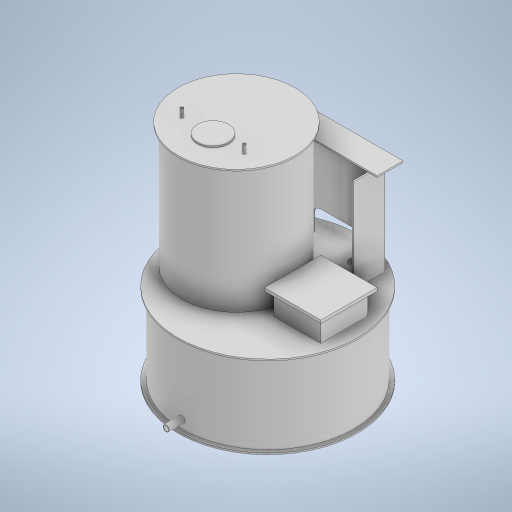
# Autodesk Inventor part: СДР 070 2хЕмкость
Saved by Autodesk Inventor 2023 (Build 270158000, 158)
## iProperties
Created: 2024-04-03
Part Number: СДР 070 2хЕмкость
Material: Типовые
Document SubType Name: Modeling
Designer: pokla
Density: 1 g/cm^3
Appearance: По умолчанию
Author: pokla
Autodesk Inventor part; units mm, degrees
ref_plane "YZ Plane" through (0, 0, 0) normal (1, 0, 0) x (0, 1, 0)
ref_plane "XZ Plane" through (0, 0, 0) normal (0, 1, 0) x (-1, 0, 0)
ref_plane "XY Plane" through (0, 0, 0) normal (0, 0, 1) x (1, 0, 0)
sketch "Эскиз1" plane through (0, 0, 0) normal (0, 1, 0) x (-1, 0, 0)
  circle A0 centre (0, 0) radius 575
  dimension "d0" = 1150
  constraints: 1 centre point, 1 coincident
  measures "d0" diameter of A0
extrude "Выдавливание1" add sketch "Эскиз1" along normal blind 10
sketch "Эскиз2" plane through (0, 10, 0) normal (0, 1, 0) x (1, 0, 0)
  circle A0 centre (0, 0) radius 550
  dimension "d3" = 1100
  constraints: 1 centre point, 1 coincident
  measures "d3" diameter of A0
extrude "Выдавливание2" add sketch "Эскиз2" along normal blind 510
sketch "Эскиз3" plane through (0, 520, 0) normal (0, 1, 0) x (1, 0, 0)
  circle A0 centre (0, 0) radius 575
  dimension "d6" = 1150
  constraints: 1 centre point, 1 coincident
  measures "d6" diameter of A0
extrude "Выдавливание3" add sketch "Эскиз3" along normal blind 10
sketch "Эскиз4" plane through (0, 530, 0) normal (0, 1, 0) x (1, 0, 0)
  circle A0 centre (0, 0) radius 550 projected
  circle A1 centre (0, 0) radius 550 projected
  line L0 (-840.1304, 0) -> (1197.9303, 0) construction
  circle A2 centre (-200, 0) radius 350
  dimension "d14" = 700
  dimension "d15" = 200
  constraints: 2 end point, 1 centre point, 1 horizontal, 1 horizontal alignment, 1 point on line
  measures "d14" diameter of A2
  measures "d15" distance of point (0, 0) A2.centre
extrude "Выдавливание4" add sketch "Эскиз4" along normal blind 800 contours A2
sketch "Эскиз5" plane through (-200, 1330, 0) normal (0, 1, 0) x (1, 0, 0)
  circle A0 centre (0, 0) radius 375
  point P0 (200, 0)
  dimension "d18" = 750
  constraints: 1 centre point
  measures "d18" diameter of A0
extrude "Выдавливание5" add sketch "Эскиз5" along normal blind 10
sketch "Эскиз7" plane through (0, 530, 0) normal (0, 1, 0) x (1, 0, 0)
  line L0 (190, 150) -> (490, 150)
  line L1 (490, 150) -> (490, -150)
  line L2 (490, -150) -> (190, -150)
  line L3 (190, -150) -> (190, 150)
  circle A0 centre (0, 0) radius 550 projected
  circle A1 centre (-200, 0) radius 350 projected
  point P0 (490, 0)
  point P1 (190, 0)
  dimension "d23" = 300
  dimension "d24" = 190
  constraints: 8 end point, 2 midpoint, 2 parallel, 2 perpendicular, 1 horizontal, 1 horizontal alignment
  measures "d23" distance of L1.end L2.end
  measures "d24" distance of point (0, 0) point (190, 0)
extrude "Выдавливание6" add sketch "Эскиз7" along normal blind 140 contours L0 L1 L2 L3
sketch "Эскиз8" plane through (0, 670, 0) normal (0, 1, 0) x (1, 0, 0)
  line L0 (190, -150) -> (490, -150) projected
  line L1 (490, -150) -> (490, 150) projected
  line L2 (490, 150) -> (190, 150) projected
  line L3 (190, 150) -> (190, -150) projected
  line L4 (160, 180) -> (520, 180)
  line L5 (520, 180) -> (520, -180)
  line L6 (520, -180) -> (160, -180)
  line L7 (160, -180) -> (160, 180)
  point P0 (0, 0)
  dimension "d27" = 30
  constraints: 8 end point, 3 other
  measures "d27" distance between parallel lines of L2 L4
extrude "Выдавливание7" add sketch "Эскиз8" along normal blind 20 contours L3 L2 L1 L0 | L4 L5 L6 L7
sketch "Эскиз9" plane through (0, 530, 0) normal (0, 1, 0) x (1, 0, 0)
  circle A0 centre (0, 0) radius 550 projected
  line L0 (490, 150) -> (190, 150) projected
  line L1 (190, 150) -> (190, -150) projected
  circle A1 centre (-200, 0) radius 350 construction
  line L2 (-300, 350) -> (-300, 450)
  line L3 (-300, 450) -> (300, 450)
  line L4 (300, 450) -> (300, 250)
  line L5 (290, 250) -> (290, 440)
  line L6 (290, 440) -> (-290, 440)
  line L7 (-290, 440) -> (-290, 350)
  line L8 (-290, 350) -> (-300, 350)
  line L9 (300, 250) -> (290, 250)
  dimension "d40" = 100
  dimension "d41" = 200
  dimension "d42" = 600
  dimension "d43" = 300
  dimension "d44" = 450
  dimension "d45" = 10
  constraints: 16 end point, 4 perpendicular, 1 horizontal, 1 parallel, 1 vertical, 2 other
  measures "d40" distance of L2.start L2.end
  measures "d41" distance of L3.end L4.end
  measures "d42" distance of L2.end L3.end
  measures "d43" distance from line of point (0, 0) L2
  measures "d44" distance from line of point (0, 0) L3
  measures "d45" distance between parallel lines of L4 L5
extrude "Выдавливание8" add sketch "Эскиз9" along normal blind 600 contours L2 L3 L4 L9 L5 L6 L7 L8
sketch "Эскиз11" plane through (0, 1130, 0) normal (0, 1, 0) x (1, 0, 0)
  line L0 (-300, 350) -> (-300, 450) projected
  line L1 (-300, 350) -> (300, 350) construction
  line L2 (300, 450) -> (300, 250) projected
  line L3 (-350, 515) -> (350, 515)
  line L4 (350, 515) -> (350, 350)
  line L5 (350, 350) -> (-350, 350)
  line L6 (-350, 350) -> (-350, 515)
  point P0 (0, 0)
  point P1 (0, 350)
  dimension "d52" = 700
  dimension "d53" = 165
  constraints: 10 end point, 3 midpoint, 2 parallel, 1 horizontal, 1 perpendicular
  measures "d52" distance of L3.start L3.end
  measures "d53" distance of L3.end L4.end
extrude "Выдавливание10" add sketch "Эскиз11" along normal blind 10
sketch "Эскиз12" plane through (300, 530, -450) normal (0, 0, -1) x (-1, 0, 0)
  line L0 (600, 0) -> (0, 0) projected
  line L1 (600, 0) -> (600, 600) projected
  line L2 (0, 600) -> (600, 600) projected
  line L3 (0, 0) -> (0, 600) projected
  line L4 (10, 0) -> (590, 0) projected
  line L5 (150, 0) -> (150, 155)
  line L6 (150, 155) -> (450, 155)
  line L7 (450, 155) -> (450, 0)
  line L8 (500, 600) -> (10, 600) projected
  point P0 (300, -530)
  point P1 (450, 56.6393)
  dimension "d58" = 300
  dimension "d59" = 155
  dimension "d61" = 150
  constraints: 6 end point, 3 point on line, 2 perpendicular
  measures "d58" distance between parallel lines of L7 L5
  measures "d59" distance between parallel lines of L0 L6
  measures "d61" distance from line of L1 point (450, 56.639)
extrude "Выдавливание11" cut sketch "Эскиз12" against normal up to surface (10 mm away) contours L0 L5 L6 L7
fillet "Сопряжение1" radius 50 2 edges at (150, 685, -445) (-150, 685, -445)
sketch "Эскиз13" plane through (0, 530, 0) normal (0, 1, 0) x (1, 0, 0)
  line L0 (150, 450) -> (150, 440) projected
  line L1 (-150, 450) -> (-150, 440) projected
  circle A0 centre (150, 400) radius 30
  line L2 (150, 440) -> (-150, 440) construction
  line L3 (-190, 450) -> (-190, 400) construction
  line L4 (-190, 400) -> (190, 400) construction
  line L5 (190, 400) -> (190, 450) construction
  line L6 (150, 440) -> (150, 328.7741) construction
  line L7 (-150, 440) -> (-150, 308.6915) construction
  circle A1 centre (-150, 400) radius 27.5
  circle A2 centre (150, 400) radius 25
  circle A3 centre (-150, 400) radius 22.5
  point P0 (0, 0)
  dimension "d66" = 60
  dimension "d67" = 40
  dimension "d68" = 55
  dimension "d69" = 5
  dimension "d70" = 5
  constraints: 12 end point, 4 centre point, 4 point on line, 2 coincident, 2 vertical, 1 horizontal, 2 other
  measures "d66" diameter of A0
  measures "d67" distance between parallel lines of L2 L4
  measures "d68" diameter of A1
  measures "d69" radial gap between concentric circles of A0 A2
  measures "d70" radial gap between concentric circles of A1 A3
extrude "Выдавливание12" add sketch "Эскиз13" along normal blind 10
sketch "Эскиз14" plane through (-150, 530, -400) normal (0, 1, 0) x (1, 0, 0)
  circle A0 centre (300, 0) radius 25 projected
  circle A1 centre (0, 0) radius 22.5 projected
  point P0 (150, -400)
extrude "Выдавливание13" cut sketch "Эскиз14" against normal blind 30
sketch "Эскиз15" plane through (0, 0, 0) normal (0, 0, 1) x (1, 0, 0)
  line L0 (575, 0) -> (-575, 0) projected
  circle A0 centre (0, 65) radius 20
  circle A1 centre (0, 65) radius 15
  point P0 (0, 0)
  point P1 (0, 0)
  dimension "d75" = 40
  dimension "d76" = 65
  dimension "d77" = 5
  constraints: 2 centre point, 1 midpoint, 1 vertical alignment
  measures "d75" diameter of A0
  measures "d76" distance of point (0, 0) A0.centre
  measures "d77" radial gap between concentric circles of A0 A1
extrude "Выдавливание14" add sketch "Эскиз15" along normal blind 650
sketch "Эскиз16" plane through (0, 0, 0) normal (1, 0, 0) x (0, 1, 0)
  line L0 (0, -575) -> (0, 575) projected
  circle A0 centre (65, 0) radius 20
  circle A1 centre (65, 0) radius 15
  line L1 (530, 350) -> (530, -350) projected
  circle A2 centre (590, 0) radius 20
  circle A3 centre (590, 0) radius 15
  point P0 (0, 0)
  point P1 (0, 0)
  point P2 (530, 0)
  dimension "d80" = 40
  dimension "d81" = 65
  dimension "d82" = 5
  dimension "d83" = 40
  dimension "d84" = 60
  dimension "d85" = 5
  constraints: 4 centre point, 2 horizontal alignment, 2 midpoint
  measures "d80" diameter of A0
  measures "d81" distance of point (0, 0) A0.centre
  measures "d82" radial gap between concentric circles of A0 A1
  measures "d83" diameter of A2
  measures "d84" distance of point (530, 0) A2.centre
  measures "d85" radial gap between concentric circles of A2 A3
extrude "Выдавливание15" add sketch "Эскиз16" against normal blind 650
sketch "Эскиз17" plane through (-200, 1340, 0) normal (0, 1, 0) x (1, 0, 0)
  circle A0 centre (0, 0) radius 350 projected
  circle A1 centre (200, 0) radius 550 construction
  line L0 (-350, 0) -> (350, 0) construction
  line L1 (360, 180) -> (360, -180) construction
  circle A2 centre (0, -150) radius 100
  dimension "d88" = 200
  dimension "d89" = 150
  constraints: 2 end point, 2 point on circle, 1 centre point, 1 horizontal alignment, 1 midpoint, 1 perpendicular, 1 vertical alignment, 1 other
  measures "d88" diameter of A2
  measures "d89" distance of A0.centre A2.centre
extrude "Выдавливание16" add sketch "Эскиз17" along normal blind 10 contours A2
sketch "Эскиз18" plane through (-200, 1340, 0) normal (0, 1, 0) x (1, 0, 0)
  circle A0 centre (0, -150) radius 100 projected
  circle A1 centre (0, 0) radius 350 projected
  circle A2 centre (200, 0) radius 550 construction
  line L0 (-350, 0) -> (350, 0) construction
  line L1 (360, 180) -> (360, -180) construction
  circle A3 centre (-200, -150) radius 10
  line L2 (0, -150) -> (-457.1961, -150) construction
  line L3 (0, -150) -> (489.8773, -150) construction
  circle A4 centre (0, 0) radius 350 construction
  circle A5 centre (200, -150) radius 10
  circle A6 centre (-200, -150) radius 8
  circle A7 centre (200, -150) radius 8
  dimension "d92" = 20
  dimension "d93" = 200
  dimension "d95" = 20
  dimension "d96" = 200
  dimension "d97" = 2
  dimension "d98" = 2
  constraints: 6 end point, 4 centre point, 2 horizontal, 2 horizontal alignment, 2 point on circle, 2 point on line, 1 perpendicular, 1 other
  measures "d92" diameter of A3
  measures "d93" distance of L2.start A3.centre
  measures "d95" diameter of A5
  measures "d96" distance of L2.start A5.centre
  measures "d97" radial gap between concentric circles of A3 A6
  measures "d98" radial gap between concentric circles of A5 A7
extrude "Выдавливание17" add sketch "Эскиз18" along normal blind 50 contours A3 | A5
